Autodesk Fusion 360 part; units mm, degrees
(part 8 of 9)
equation "d522 = abs(( 0 ) * ( ( ( -1 ) * jointNodeQ * sqrt(2) - bodyWidth / 2 * cos(225 deg) + ( ( 1 ) * nodeHalfWidth ) * sin(225 deg) ) + ( 0.666666666666667 ) * ( ( -1 ) * endNodeX - ( ( -1 ) * jointNodeQ * sqrt(2) - bodyWidth / 2 * cos(225 deg) + ( ( 1 ) * nodeHalfWidth ) * sin(225 deg) ) ) ) + ( -1 ) * ( ( 1 ) * nodeHalfWidth ))"
equation "d523 = abs(( 1 ) * ( ( ( -1 ) * jointNodeQ * sqrt(2) - bodyWidth / 2 * cos(225 deg) + ( ( -1 ) * nodeHalfWidth ) * sin(225 deg) ) + ( 1 ) * ( ( -1 ) * endNodeX - ( ( -1 ) * jointNodeQ * sqrt(2) - bodyWidth / 2 * cos(225 deg) + ( ( -1 ) * nodeHalfWidth ) * sin(225 deg) ) ) ) + ( 0 ) * ( ( -1 ) * nodeHalfWidth ))"
equation "d524 = abs(( 0 ) * ( ( ( -1 ) * jointNodeQ * sqrt(2) - bodyWidth / 2 * cos(225 deg) + ( ( -1 ) * nodeHalfWidth ) * sin(225 deg) ) + ( 1 ) * ( ( -1 ) * endNodeX - ( ( -1 ) * jointNodeQ * sqrt(2) - bodyWidth / 2 * cos(225 deg) + ( ( -1 ) * nodeHalfWidth ) * sin(225 deg) ) ) ) + ( -1 ) * ( ( -1 ) * nodeHalfWidth ))"
equation "d525 = memberWidth / 2"
equation "d526 = -( wall + 0.2 mm )"
equation "d528 = abs(( 1 ) * ( ( ( -1 ) * jointNodeQ * sqrt(2) - bodyWidth / 2 * cos(225 deg) + ( ( 1 ) * nodeHalfWidth ) * sin(225 deg) ) + ( 0.666666666666667 ) * ( ( -1 ) * endNodeX - ( ( -1 ) * jointNodeQ * sqrt(2) - bodyWidth / 2 * cos(225 deg) + ( ( 1 ) * nodeHalfWidth ) * sin(225 deg) ) ) ) + ( 0 ) * ( ( 1 ) * nodeHalfWidth ))"
equation "d529 = abs(( 0 ) * ( ( ( -1 ) * jointNodeQ * sqrt(2) - bodyWidth / 2 * cos(225 deg) + ( ( 1 ) * nodeHalfWidth ) * sin(225 deg) ) + ( 0.666666666666667 ) * ( ( -1 ) * endNodeX - ( ( -1 ) * jointNodeQ * sqrt(2) - bodyWidth / 2 * cos(225 deg) + ( ( 1 ) * nodeHalfWidth ) * sin(225 deg) ) ) ) + ( -1 ) * ( ( 1 ) * nodeHalfWidth ))"
equation "d530 = abs(( 1 ) * ( ( ( -1 ) * jointNodeQ * sqrt(2) - bodyWidth / 2 * cos(225 deg) + ( ( -1 ) * nodeHalfWidth ) * sin(225 deg) ) + ( 1 ) * ( ( -1 ) * endNodeX - ( ( -1 ) * jointNodeQ * sqrt(2) - bodyWidth / 2 * cos(225 deg) + ( ( -1 ) * nodeHalfWidth ) * sin(225 deg) ) ) ) + ( 0 ) * ( ( -1 ) * nodeHalfWidth ))"
equation "d531 = abs(( 0 ) * ( ( ( -1 ) * jointNodeQ * sqrt(2) - bodyWidth / 2 * cos(225 deg) + ( ( -1 ) * nodeHalfWidth ) * sin(225 deg) ) + ( 1 ) * ( ( -1 ) * endNodeX - ( ( -1 ) * jointNodeQ * sqrt(2) - bodyWidth / 2 * cos(225 deg) + ( ( -1 ) * nodeHalfWidth ) * sin(225 deg) ) ) ) + ( -1 ) * ( ( -1 ) * nodeHalfWidth ))"
equation "d532 = abs(( 1 ) * ( ( ( -1 ) * jointNodeQ * sqrt(2) - bodyWidth / 2 * cos(225 deg) + ( ( 1 ) * nodeHalfWidth ) * sin(225 deg) ) + ( 1 ) * ( ( -1 ) * endNodeX - ( ( -1 ) * jointNodeQ * sqrt(2) - bodyWidth / 2 * cos(225 deg) + ( ( 1 ) * nodeHalfWidth ) * sin(225 deg) ) ) ) + ( 0 ) * ( ( 1 ) * nodeHalfWidth ))"
equation "d533 = abs(( 0 ) * ( ( ( -1 ) * jointNodeQ * sqrt(2) - bodyWidth / 2 * cos(225 deg) + ( ( 1 ) * nodeHalfWidth ) * sin(225 deg) ) + ( 1 ) * ( ( -1 ) * endNodeX - ( ( -1 ) * jointNodeQ * sqrt(2) - bodyWidth / 2 * cos(225 deg) + ( ( 1 ) * nodeHalfWidth ) * sin(225 deg) ) ) ) + ( -1 ) * ( ( 1 ) * nodeHalfWidth ))"
equation "d534 = -memberWidth / 2"
equation "d535 = -( wall + 0.2 mm )"
equation "d538 = apertureRadius"
equation "d541 = bodyWidth / 2"
equation "d543 = abs(( -1 ) * ( ( ( -1 ) * jointNodeQ * sqrt(2) - bodyWidth / 2 * cos(270 deg) + ( ( -1 ) * nodeHalfWidth ) * sin(270 deg) ) + ( 0 ) * ( ( -1 ) * endNodeX - ( ( -1 ) * jointNodeQ * sqrt(2) - bodyWidth / 2 * cos(270 deg) + ( ( -1 ) * nodeHalfWidth ) * sin(270 deg) ) ) ) + ( 0 ) * ( ( -1 ) * nodeHalfWidth ))"
equation "d544 = abs(( 0 ) * ( ( ( -1 ) * jointNodeQ * sqrt(2) - bodyWidth / 2 * cos(270 deg) + ( ( -1 ) * nodeHalfWidth ) * sin(270 deg) ) + ( 0 ) * ( ( -1 ) * endNodeX - ( ( -1 ) * jointNodeQ * sqrt(2) - bodyWidth / 2 * cos(270 deg) + ( ( -1 ) * nodeHalfWidth ) * sin(270 deg) ) ) ) + ( 1 ) * ( ( -1 ) * nodeHalfWidth ))"
equation "d545 = abs(( -1 ) * ( ( ( -1 ) * jointNodeQ * sqrt(2) - bodyWidth / 2 * cos(270 deg) + ( ( 1 ) * nodeHalfWidth ) * sin(270 deg) ) + ( 0 ) * ( ( -1 ) * endNodeX - ( ( -1 ) * jointNodeQ * sqrt(2) - bodyWidth / 2 * cos(270 deg) + ( ( 1 ) * nodeHalfWidth ) * sin(270 deg) ) ) ) + ( 0 ) * ( ( 1 ) * nodeHalfWidth ))"
equation "d546 = abs(( 0 ) * ( ( ( -1 ) * jointNodeQ * sqrt(2) - bodyWidth / 2 * cos(270 deg) + ( ( 1 ) * nodeHalfWidth ) * sin(270 deg) ) + ( 0 ) * ( ( -1 ) * endNodeX - ( ( -1 ) * jointNodeQ * sqrt(2) - bodyWidth / 2 * cos(270 deg) + ( ( 1 ) * nodeHalfWidth ) * sin(270 deg) ) ) ) + ( 1 ) * ( ( 1 ) * nodeHalfWidth ))"
equation "d547 = abs(( -1 ) * ( ( ( -1 ) * jointNodeQ * sqrt(2) - bodyWidth / 2 * cos(270 deg) + ( ( -1 ) * nodeHalfWidth ) * sin(270 deg) ) + ( 0.5 ) * ( ( -1 ) * endNodeX - ( ( -1 ) * jointNodeQ * sqrt(2) - bodyWidth / 2 * cos(270 deg) + ( ( -1 ) * nodeHalfWidth ) * sin(270 deg) ) ) ) + ( 0 ) * ( ( -1 ) * nodeHalfWidth ))"
equation "d548 = abs(( 0 ) * ( ( ( -1 ) * jointNodeQ * sqrt(2) - bodyWidth / 2 * cos(270 deg) + ( ( -1 ) * nodeHalfWidth ) * sin(270 deg) ) + ( 0.5 ) * ( ( -1 ) * endNodeX - ( ( -1 ) * jointNodeQ * sqrt(2) - bodyWidth / 2 * cos(270 deg) + ( ( -1 ) * nodeHalfWidth ) * sin(270 deg) ) ) ) + ( 1 ) * ( ( -1 ) * nodeHalfWidth ))"
equation "d549 = memberWidth / 2"
equation "d550 = -( wall + 0.2 mm )"
equation "d552 = abs(( -1 ) * ( ( ( -1 ) * jointNodeQ * sqrt(2) - bodyWidth / 2 * cos(270 deg) + ( ( 1 ) * nodeHalfWidth ) * sin(270 deg) ) + ( 0 ) * ( ( -1 ) * endNodeX - ( ( -1 ) * jointNodeQ * sqrt(2) - bodyWidth / 2 * cos(270 deg) + ( ( 1 ) * nodeHalfWidth ) * sin(270 deg) ) ) ) + ( 0 ) * ( ( 1 ) * nodeHalfWidth ))"
equation "d553 = abs(( 0 ) * ( ( ( -1 ) * jointNodeQ * sqrt(2) - bodyWidth / 2 * cos(270 deg) + ( ( 1 ) * nodeHalfWidth ) * sin(270 deg) ) + ( 0 ) * ( ( -1 ) * endNodeX - ( ( -1 ) * jointNodeQ * sqrt(2) - bodyWidth / 2 * cos(270 deg) + ( ( 1 ) * nodeHalfWidth ) * sin(270 deg) ) ) ) + ( 1 ) * ( ( 1 ) * nodeHalfWidth ))"
equation "d554 = abs(( -1 ) * ( ( ( -1 ) * jointNodeQ * sqrt(2) - bodyWidth / 2 * cos(270 deg) + ( ( -1 ) * nodeHalfWidth ) * sin(270 deg) ) + ( 0.5 ) * ( ( -1 ) * endNodeX - ( ( -1 ) * jointNodeQ * sqrt(2) - bodyWidth / 2 * cos(270 deg) + ( ( -1 ) * nodeHalfWidth ) * sin(270 deg) ) ) ) + ( 0 ) * ( ( -1 ) * nodeHalfWidth ))"
equation "d555 = abs(( 0 ) * ( ( ( -1 ) * jointNodeQ * sqrt(2) - bodyWidth / 2 * cos(270 deg) + ( ( -1 ) * nodeHalfWidth ) * sin(270 deg) ) + ( 0.5 ) * ( ( -1 ) * endNodeX - ( ( -1 ) * jointNodeQ * sqrt(2) - bodyWidth / 2 * cos(270 deg) + ( ( -1 ) * nodeHalfWidth ) * sin(270 deg) ) ) ) + ( 1 ) * ( ( -1 ) * nodeHalfWidth ))"
equation "d556 = abs(( -1 ) * ( ( ( -1 ) * jointNodeQ * sqrt(2) - bodyWidth / 2 * cos(270 deg) + ( ( 1 ) * nodeHalfWidth ) * sin(270 deg) ) + ( 1 ) * ( ( -1 ) * endNodeX - ( ( -1 ) * jointNodeQ * sqrt(2) - bodyWidth / 2 * cos(270 deg) + ( ( 1 ) * nodeHalfWidth ) * sin(270 deg) ) ) ) + ( 0 ) * ( ( 1 ) * nodeHalfWidth ))"
equation "d557 = abs(( 0 ) * ( ( ( -1 ) * jointNodeQ * sqrt(2) - bodyWidth / 2 * cos(270 deg) + ( ( 1 ) * nodeHalfWidth ) * sin(270 deg) ) + ( 1 ) * ( ( -1 ) * endNodeX - ( ( -1 ) * jointNodeQ * sqrt(2) - bodyWidth / 2 * cos(270 deg) + ( ( 1 ) * nodeHalfWidth ) * sin(270 deg) ) ) ) + ( 1 ) * ( ( 1 ) * nodeHalfWidth ))"
equation "d558 = -memberWidth / 2"
equation "d559 = -( wall + 0.2 mm )"
equation "d561 = abs(( -1 ) * ( ( ( -1 ) * jointNodeQ * sqrt(2) - bodyWidth / 2 * cos(270 deg) + ( ( -1 ) * nodeHalfWidth ) * sin(270 deg) ) + ( 0.5 ) * ( ( -1 ) * endNodeX - ( ( -1 ) * jointNodeQ * sqrt(2) - bodyWidth / 2 * cos(270 deg) + ( ( -1 ) * nodeHalfWidth ) * sin(270 deg) ) ) ) + ( 0 ) * ( ( -1 ) * nodeHalfWidth ))"
equation "d562 = abs(( 0 ) * ( ( ( -1 ) * jointNodeQ * sqrt(2) - bodyWidth / 2 * cos(270 deg) + ( ( -1 ) * nodeHalfWidth ) * sin(270 deg) ) + ( 0.5 ) * ( ( -1 ) * endNodeX - ( ( -1 ) * jointNodeQ * sqrt(2) - bodyWidth / 2 * cos(270 deg) + ( ( -1 ) * nodeHalfWidth ) * sin(270 deg) ) ) ) + ( 1 ) * ( ( -1 ) * nodeHalfWidth ))"
equation "d563 = abs(( -1 ) * ( ( ( -1 ) * jointNodeQ * sqrt(2) - bodyWidth / 2 * cos(270 deg) + ( ( 1 ) * nodeHalfWidth ) * sin(270 deg) ) + ( 1 ) * ( ( -1 ) * endNodeX - ( ( -1 ) * jointNodeQ * sqrt(2) - bodyWidth / 2 * cos(270 deg) + ( ( 1 ) * nodeHalfWidth ) * sin(270 deg) ) ) ) + ( 0 ) * ( ( 1 ) * nodeHalfWidth ))"
equation "d564 = abs(( 0 ) * ( ( ( -1 ) * jointNodeQ * sqrt(2) - bodyWidth / 2 * cos(270 deg) + ( ( 1 ) * nodeHalfWidth ) * sin(270 deg) ) + ( 1 ) * ( ( -1 ) * endNodeX - ( ( -1 ) * jointNodeQ * sqrt(2) - bodyWidth / 2 * cos(270 deg) + ( ( 1 ) * nodeHalfWidth ) * sin(270 deg) ) ) ) + ( 1 ) * ( ( 1 ) * nodeHalfWidth ))"
equation "d565 = abs(( -1 ) * ( ( ( -1 ) * jointNodeQ * sqrt(2) - bodyWidth / 2 * cos(270 deg) + ( ( -1 ) * nodeHalfWidth ) * sin(270 deg) ) + ( 1 ) * ( ( -1 ) * endNodeX - ( ( -1 ) * jointNodeQ * sqrt(2) - bodyWidth / 2 * cos(270 deg) + ( ( -1 ) * nodeHalfWidth ) * sin(270 deg) ) ) ) + ( 0 ) * ( ( -1 ) * nodeHalfWidth ))"
equation "d566 = abs(( 0 ) * ( ( ( -1 ) * jointNodeQ * sqrt(2) - bodyWidth / 2 * cos(270 deg) + ( ( -1 ) * nodeHalfWidth ) * sin(270 deg) ) + ( 1 ) * ( ( -1 ) * endNodeX - ( ( -1 ) * jointNodeQ * sqrt(2) - bodyWidth / 2 * cos(270 deg) + ( ( -1 ) * nodeHalfWidth ) * sin(270 deg) ) ) ) + ( 1 ) * ( ( -1 ) * nodeHalfWidth ))"
equation "d567 = memberWidth / 2"
equation "d568 = -( wall + 0.2 mm )"
equation "d571 = apertureRadius"
equation "d574 = bodyWidth / 2"
equation "d576 = abs(( 1 ) * ( ( ( -1 ) * jointNodeQ * sqrt(2) - bodyWidth / 2 * cos(315 deg) + ( ( -1 ) * nodeHalfWidth ) * sin(315 deg) ) + ( 0 ) * ( ( -1 ) * endNodeX - ( ( -1 ) * jointNodeQ * sqrt(2) - bodyWidth / 2 * cos(315 deg) + ( ( -1 ) * nodeHalfWidth ) * sin(315 deg) ) ) ) + ( 0 ) * ( ( -1 ) * nodeHalfWidth ))"
equation "d577 = abs(( 0 ) * ( ( ( -1 ) * jointNodeQ * sqrt(2) - bodyWidth / 2 * cos(315 deg) + ( ( -1 ) * nodeHalfWidth ) * sin(315 deg) ) + ( 0 ) * ( ( -1 ) * endNodeX - ( ( -1 ) * jointNodeQ * sqrt(2) - bodyWidth / 2 * cos(315 deg) + ( ( -1 ) * nodeHalfWidth ) * sin(315 deg) ) ) ) + ( -1 ) * ( ( -1 ) * nodeHalfWidth ))"
equation "d578 = abs(( 1 ) * ( ( ( -1 ) * jointNodeQ * sqrt(2) - bodyWidth / 2 * cos(315 deg) + ( ( 1 ) * nodeHalfWidth ) * sin(315 deg) ) + ( 0 ) * ( ( -1 ) * endNodeX - ( ( -1 ) * jointNodeQ * sqrt(2) - bodyWidth / 2 * cos(315 deg) + ( ( 1 ) * nodeHalfWidth ) * sin(315 deg) ) ) ) + ( 0 ) * ( ( 1 ) * nodeHalfWidth ))"
equation "d579 = abs(( 0 ) * ( ( ( -1 ) * jointNodeQ * sqrt(2) - bodyWidth / 2 * cos(315 deg) + ( ( 1 ) * nodeHalfWidth ) * sin(315 deg) ) + ( 0 ) * ( ( -1 ) * endNodeX - ( ( -1 ) * jointNodeQ * sqrt(2) - bodyWidth / 2 * cos(315 deg) + ( ( 1 ) * nodeHalfWidth ) * sin(315 deg) ) ) ) + ( -1 ) * ( ( 1 ) * nodeHalfWidth ))"
equation "d580 = abs(( 1 ) * ( ( ( -1 ) * jointNodeQ * sqrt(2) - bodyWidth / 2 * cos(315 deg) + ( ( -1 ) * nodeHalfWidth ) * sin(315 deg) ) + ( 1 ) * ( ( -1 ) * endNodeX - ( ( -1 ) * jointNodeQ * sqrt(2) - bodyWidth / 2 * cos(315 deg) + ( ( -1 ) * nodeHalfWidth ) * sin(315 deg) ) ) ) + ( 0 ) * ( ( -1 ) * nodeHalfWidth ))"
equation "d581 = abs(( 0 ) * ( ( ( -1 ) * jointNodeQ * sqrt(2) - bodyWidth / 2 * cos(315 deg) + ( ( -1 ) * nodeHalfWidth ) * sin(315 deg) ) + ( 1 ) * ( ( -1 ) * endNodeX - ( ( -1 ) * jointNodeQ * sqrt(2) - bodyWidth / 2 * cos(315 deg) + ( ( -1 ) * nodeHalfWidth ) * sin(315 deg) ) ) ) + ( -1 ) * ( ( -1 ) * nodeHalfWidth ))"
equation "d582 = memberWidth / 2"
equation "d583 = -( wall + 0.2 mm )"
equation "d585 = abs(( 1 ) * ( ( ( -1 ) * jointNodeQ * sqrt(2) - bodyWidth / 2 * cos(315 deg) + ( ( 1 ) * nodeHalfWidth ) * sin(315 deg) ) + ( 0 ) * ( ( -1 ) * endNodeX - ( ( -1 ) * jointNodeQ * sqrt(2) - bodyWidth / 2 * cos(315 deg) + ( ( 1 ) * nodeHalfWidth ) * sin(315 deg) ) ) ) + ( 0 ) * ( ( 1 ) * nodeHalfWidth ))"
equation "d586 = abs(( 0 ) * ( ( ( -1 ) * jointNodeQ * sqrt(2) - bodyWidth / 2 * cos(315 deg) + ( ( 1 ) * nodeHalfWidth ) * sin(315 deg) ) + ( 0 ) * ( ( -1 ) * endNodeX - ( ( -1 ) * jointNodeQ * sqrt(2) - bodyWidth / 2 * cos(315 deg) + ( ( 1 ) * nodeHalfWidth ) * sin(315 deg) ) ) ) + ( -1 ) * ( ( 1 ) * nodeHalfWidth ))"
equation "d587 = abs(( 1 ) * ( ( ( -1 ) * jointNodeQ * sqrt(2) - bodyWidth / 2 * cos(315 deg) + ( ( -1 ) * nodeHalfWidth ) * sin(315 deg) ) + ( 1 ) * ( ( -1 ) * endNodeX - ( ( -1 ) * jointNodeQ * sqrt(2) - bodyWidth / 2 * cos(315 deg) + ( ( -1 ) * nodeHalfWidth ) * sin(315 deg) ) ) ) + ( 0 ) * ( ( -1 ) * nodeHalfWidth ))"
equation "d588 = abs(( 0 ) * ( ( ( -1 ) * jointNodeQ * sqrt(2) - bodyWidth / 2 * cos(315 deg) + ( ( -1 ) * nodeHalfWidth ) * sin(315 deg) ) + ( 1 ) * ( ( -1 ) * endNodeX - ( ( -1 ) * jointNodeQ * sqrt(2) - bodyWidth / 2 * cos(315 deg) + ( ( -1 ) * nodeHalfWidth ) * sin(315 deg) ) ) ) + ( -1 ) * ( ( -1 ) * nodeHalfWidth ))"
equation "d589 = abs(( 1 ) * ( ( ( -1 ) * jointNodeQ * sqrt(2) - bodyWidth / 2 * cos(315 deg) + ( ( 1 ) * nodeHalfWidth ) * sin(315 deg) ) + ( 1 ) * ( ( -1 ) * endNodeX - ( ( -1 ) * jointNodeQ * sqrt(2) - bodyWidth / 2 * cos(315 deg) + ( ( 1 ) * nodeHalfWidth ) * sin(315 deg) ) ) ) + ( 0 ) * ( ( 1 ) * nodeHalfWidth ))"
equation "d590 = abs(( 0 ) * ( ( ( -1 ) * jointNodeQ * sqrt(2) - bodyWidth / 2 * cos(315 deg) + ( ( 1 ) * nodeHalfWidth ) * sin(315 deg) ) + ( 1 ) * ( ( -1 ) * endNodeX - ( ( -1 ) * jointNodeQ * sqrt(2) - bodyWidth / 2 * cos(315 deg) + ( ( 1 ) * nodeHalfWidth ) * sin(315 deg) ) ) ) + ( -1 ) * ( ( 1 ) * nodeHalfWidth ))"
equation "d591 = -memberWidth / 2"
equation "d592 = -( wall + 0.2 mm )"
equation "d595 = apertureRadius"
equation "d596 = qFront"
equation "d598 = carrierOD"
equation "d599 = spokeDepth"
equation "d601 = qFront"
equation "d603 = abs(( 0 mm ) * ( cos(-73.6750500631048 deg) ) - ( -1 ) * spokeWidth / 2 * ( sin(-73.6750500631048 deg) ))"
equation "d604 = abs(( 0 mm ) * ( sin(-73.6750500631048 deg) ) + ( -1 ) * spokeWidth / 2 * ( cos(-73.6750500631048 deg) ))"
equation "d605 = abs(( bodyWidth ) * ( cos(-73.6750500631048 deg) ) - ( -1 ) * spokeWidth / 2 * ( sin(-73.6750500631048 deg) ))"
equation "d606 = abs(( bodyWidth ) * ( sin(-73.6750500631048 deg) ) + ( -1 ) * spokeWidth / 2 * ( cos(-73.6750500631048 deg) ))"
equation "d607 = abs(( bodyWidth ) * ( cos(-73.6750500631048 deg) ) - ( 1 ) * spokeWidth / 2 * ( sin(-73.6750500631048 deg) ))"
equation "d608 = abs(( bodyWidth ) * ( sin(-73.6750500631048 deg) ) + ( 1 ) * spokeWidth / 2 * ( cos(-73.6750500631048 deg) ))"
equation "d609 = abs(( 0 mm ) * ( cos(-73.6750500631048 deg) ) - ( 1 ) * spokeWidth / 2 * ( sin(-73.6750500631048 deg) ))"
equation "d610 = abs(( 0 mm ) * ( sin(-73.6750500631048 deg) ) + ( 1 ) * spokeWidth / 2 * ( cos(-73.6750500631048 deg) ))"
equation "d611 = spokeDepth"
equation "d613 = abs(( 0 mm ) * ( cos(-30.3611934048217 deg) ) - ( -1 ) * spokeWidth / 2 * ( sin(-30.3611934048217 deg) ))"
equation "d614 = abs(( 0 mm ) * ( sin(-30.3611934048217 deg) ) + ( -1 ) * spokeWidth / 2 * ( cos(-30.3611934048217 deg) ))"
equation "d615 = abs(( bodyWidth ) * ( cos(-30.3611934048217 deg) ) - ( -1 ) * spokeWidth / 2 * ( sin(-30.3611934048217 deg) ))"
equation "d616 = abs(( bodyWidth ) * ( sin(-30.3611934048217 deg) ) + ( -1 ) * spokeWidth / 2 * ( cos(-30.3611934048217 deg) ))"
equation "d617 = abs(( bodyWidth ) * ( cos(-30.3611934048217 deg) ) - ( 1 ) * spokeWidth / 2 * ( sin(-30.3611934048217 deg) ))"
equation "d618 = abs(( bodyWidth ) * ( sin(-30.3611934048217 deg) ) + ( 1 ) * spokeWidth / 2 * ( cos(-30.3611934048217 deg) ))"
equation "d619 = abs(( 0 mm ) * ( cos(-30.3611934048217 deg) ) - ( 1 ) * spokeWidth / 2 * ( sin(-30.3611934048217 deg) ))"
equation "d620 = abs(( 0 mm ) * ( sin(-30.3611934048217 deg) ) + ( 1 ) * spokeWidth / 2 * ( cos(-30.3611934048217 deg) ))"
equation "d621 = spokeDepth"
equation "d623 = abs(( 0 mm ) * ( cos(30.3611934048217 deg) ) - ( -1 ) * spokeWidth / 2 * ( sin(30.3611934048217 deg) ))"
equation "d624 = abs(( 0 mm ) * ( sin(30.3611934048217 deg) ) + ( -1 ) * spokeWidth / 2 * ( cos(30.3611934048217 deg) ))"
equation "d625 = abs(( bodyWidth ) * ( cos(30.3611934048217 deg) ) - ( -1 ) * spokeWidth / 2 * ( sin(30.3611934048217 deg) ))"
equation "d626 = abs(( bodyWidth ) * ( sin(30.3611934048217 deg) ) + ( -1 ) * spokeWidth / 2 * ( cos(30.3611934048217 deg) ))"
equation "d627 = abs(( bodyWidth ) * ( cos(30.3611934048217 deg) ) - ( 1 ) * spokeWidth / 2 * ( sin(30.3611934048217 deg) ))"
equation "d628 = abs(( bodyWidth ) * ( sin(30.3611934048217 deg) ) + ( 1 ) * spokeWidth / 2 * ( cos(30.3611934048217 deg) ))"
equation "d629 = abs(( 0 mm ) * ( cos(30.3611934048217 deg) ) - ( 1 ) * spokeWidth / 2 * ( sin(30.3611934048217 deg) ))"
equation "d630 = abs(( 0 mm ) * ( sin(30.3611934048217 deg) ) + ( 1 ) * spokeWidth / 2 * ( cos(30.3611934048217 deg) ))"
equation "d631 = spokeDepth"
equation "d633 = abs(( 0 mm ) * ( cos(73.6750500631048 deg) ) - ( -1 ) * spokeWidth / 2 * ( sin(73.6750500631048 deg) ))"
equation "d634 = abs(( 0 mm ) * ( sin(73.6750500631048 deg) ) + ( -1 ) * spokeWidth / 2 * ( cos(73.6750500631048 deg) ))"
equation "d635 = abs(( bodyWidth ) * ( cos(73.6750500631048 deg) ) - ( -1 ) * spokeWidth / 2 * ( sin(73.6750500631048 deg) ))"
equation "d636 = abs(( bodyWidth ) * ( sin(73.6750500631048 deg) ) + ( -1 ) * spokeWidth / 2 * ( cos(73.6750500631048 deg) ))"
equation "d637 = abs(( bodyWidth ) * ( cos(73.6750500631048 deg) ) - ( 1 ) * spokeWidth / 2 * ( sin(73.6750500631048 deg) ))"
equation "d638 = abs(( bodyWidth ) * ( sin(73.6750500631048 deg) ) + ( 1 ) * spokeWidth / 2 * ( cos(73.6750500631048 deg) ))"
equation "d639 = abs(( 0 mm ) * ( cos(73.6750500631048 deg) ) - ( 1 ) * spokeWidth / 2 * ( sin(73.6750500631048 deg) ))"
equation "d640 = abs(( 0 mm ) * ( sin(73.6750500631048 deg) ) + ( 1 ) * spokeWidth / 2 * ( cos(73.6750500631048 deg) ))"
equation "d641 = spokeDepth"
equation "d643 = abs(( 0 mm ) * ( cos(106.324949936895 deg) ) - ( -1 ) * spokeWidth / 2 * ( sin(106.324949936895 deg) ))"
equation "d644 = abs(( 0 mm ) * ( sin(106.324949936895 deg) ) + ( -1 ) * spokeWidth / 2 * ( cos(106.324949936895 deg) ))"
equation "d645 = abs(( bodyWidth ) * ( cos(106.324949936895 deg) ) - ( -1 ) * spokeWidth / 2 * ( sin(106.324949936895 deg) ))"
equation "d646 = abs(( bodyWidth ) * ( sin(106.324949936895 deg) ) + ( -1 ) * spokeWidth / 2 * ( cos(106.324949936895 deg) ))"
equation "d647 = abs(( bodyWidth ) * ( cos(106.324949936895 deg) ) - ( 1 ) * spokeWidth / 2 * ( sin(106.324949936895 deg) ))"
equation "d648 = abs(( bodyWidth ) * ( sin(106.324949936895 deg) ) + ( 1 ) * spokeWidth / 2 * ( cos(106.324949936895 deg) ))"
equation "d649 = abs(( 0 mm ) * ( cos(106.324949936895 deg) ) - ( 1 ) * spokeWidth / 2 * ( sin(106.324949936895 deg) ))"
equation "d650 = abs(( 0 mm ) * ( sin(106.324949936895 deg) ) + ( 1 ) * spokeWidth / 2 * ( cos(106.324949936895 deg) ))"
equation "d651 = spokeDepth"
equation "d653 = abs(( 0 mm ) * ( cos(149.638806595178 deg) ) - ( -1 ) * spokeWidth / 2 * ( sin(149.638806595178 deg) ))"
equation "d654 = abs(( 0 mm ) * ( sin(149.638806595178 deg) ) + ( -1 ) * spokeWidth / 2 * ( cos(149.638806595178 deg) ))"
equation "d655 = abs(( bodyWidth ) * ( cos(149.638806595178 deg) ) - ( -1 ) * spokeWidth / 2 * ( sin(149.638806595178 deg) ))"
equation "d656 = abs(( bodyWidth ) * ( sin(149.638806595178 deg) ) + ( -1 ) * spokeWidth / 2 * ( cos(149.638806595178 deg) ))"
equation "d657 = abs(( bodyWidth ) * ( cos(149.638806595178 deg) ) - ( 1 ) * spokeWidth / 2 * ( sin(149.638806595178 deg) ))"
equation "d658 = abs(( bodyWidth ) * ( sin(149.638806595178 deg) ) + ( 1 ) * spokeWidth / 2 * ( cos(149.638806595178 deg) ))"
equation "d659 = abs(( 0 mm ) * ( cos(149.638806595178 deg) ) - ( 1 ) * spokeWidth / 2 * ( sin(149.638806595178 deg) ))"
equation "d660 = abs(( 0 mm ) * ( sin(149.638806595178 deg) ) + ( 1 ) * spokeWidth / 2 * ( cos(149.638806595178 deg) ))"
equation "d661 = spokeDepth"
equation "d663 = abs(( 0 mm ) * ( cos(-149.638806595178 deg) ) - ( -1 ) * spokeWidth / 2 * ( sin(-149.638806595178 deg) ))"
equation "d664 = abs(( 0 mm ) * ( sin(-149.638806595178 deg) ) + ( -1 ) * spokeWidth / 2 * ( cos(-149.638806595178 deg) ))"
equation "d665 = abs(( bodyWidth ) * ( cos(-149.638806595178 deg) ) - ( -1 ) * spokeWidth / 2 * ( sin(-149.638806595178 deg) ))"
equation "d666 = abs(( bodyWidth ) * ( sin(-149.638806595178 deg) ) + ( -1 ) * spokeWidth / 2 * ( cos(-149.638806595178 deg) ))"
equation "d667 = abs(( bodyWidth ) * ( cos(-149.638806595178 deg) ) - ( 1 ) * spokeWidth / 2 * ( sin(-149.638806595178 deg) ))"
equation "d668 = abs(( bodyWidth ) * ( sin(-149.638806595178 deg) ) + ( 1 ) * spokeWidth / 2 * ( cos(-149.638806595178 deg) ))"
equation "d669 = abs(( 0 mm ) * ( cos(-149.638806595178 deg) ) - ( 1 ) * spokeWidth / 2 * ( sin(-149.638806595178 deg) ))"
equation "d670 = abs(( 0 mm ) * ( sin(-149.638806595178 deg) ) + ( 1 ) * spokeWidth / 2 * ( cos(-149.638806595178 deg) ))"
equation "d671 = spokeDepth"
equation "d673 = abs(( 0 mm ) * ( cos(-106.324949936895 deg) ) - ( -1 ) * spokeWidth / 2 * ( sin(-106.324949936895 deg) ))"
equation "d674 = abs(( 0 mm ) * ( sin(-106.324949936895 deg) ) + ( -1 ) * spokeWidth / 2 * ( cos(-106.324949936895 deg) ))"
equation "d675 = abs(( bodyWidth ) * ( cos(-106.324949936895 deg) ) - ( -1 ) * spokeWidth / 2 * ( sin(-106.324949936895 deg) ))"
equation "d676 = abs(( bodyWidth ) * ( sin(-106.324949936895 deg) ) + ( -1 ) * spokeWidth / 2 * ( cos(-106.324949936895 deg) ))"
equation "d677 = abs(( bodyWidth ) * ( cos(-106.324949936895 deg) ) - ( 1 ) * spokeWidth / 2 * ( sin(-106.324949936895 deg) ))"
equation "d678 = abs(( bodyWidth ) * ( sin(-106.324949936895 deg) ) + ( 1 ) * spokeWidth / 2 * ( cos(-106.324949936895 deg) ))"
equation "d679 = abs(( 0 mm ) * ( cos(-106.324949936895 deg) ) - ( 1 ) * spokeWidth / 2 * ( sin(-106.324949936895 deg) ))"
equation "d680 = abs(( 0 mm ) * ( sin(-106.324949936895 deg) ) + ( 1 ) * spokeWidth / 2 * ( cos(-106.324949936895 deg) ))"
equation "d681 = spokeDepth"
equation "d683 = bodyWidth"
equation "d684 = bodyLength"
equation "d687 = rootRadius"
equation "d688 = qFrontBack"
equation "d690 = rearCarrierClearance"
equation "d691 = spokeDepth"
equation "d693 = qFront"
equation "d695 = raceRelief"
equation "d696 = frontSeatDepth + shoulder"
equation "d698 = qFront"
equation "d700 = seatDiameter"
equation "d701 = frontSeatDepth"
equation "d703 = qFront"
equation "d705 = supportCircle / 2"
equation "d706 = m3Clearance"
equation "d707 = frontSeatDepth + shoulder"
equation "d711 = qFront"
equation "d713 = coreOD"
equation "d714 = entryChamfer"
equation "d715 = bodyWidth / 2"
equation "d717 = abs(( 16 mm + ( -6.5 mm ) ) / sqrt(2))"
equation "d718 = abs(( 16 mm - ( -6.5 mm ) ) / sqrt(2))"
equation "d720 = abs(( 16 mm + ( 6.5 mm ) ) / sqrt(2))"
equation "d721 = abs(( 16 mm - ( 6.5 mm ) ) / sqrt(2))"
equation "d723 = -( bodyWidth / 2 )"
equation "d725 = -qFront"
equation "d727 = mountOD"
equation "d728 = -( -qFront - hubFace )"
equation "d730 = -qFront"
equation "d732 = abs(( 0 mm ) * ( cos(-73.6750500631048 deg) ) - ( -1 ) * spokeWidth / 2 * ( sin(-73.6750500631048 deg) ))"
equation "d733 = abs(( 0 mm ) * ( sin(-73.6750500631048 deg) ) + ( -1 ) * spokeWidth / 2 * ( cos(-73.6750500631048 deg) ))"
equation "d734 = abs(( bodyWidth ) * ( cos(-73.6750500631048 deg) ) - ( -1 ) * spokeWidth / 2 * ( sin(-73.6750500631048 deg) ))"
equation "d735 = abs(( bodyWidth ) * ( sin(-73.6750500631048 deg) ) + ( -1 ) * spokeWidth / 2 * ( cos(-73.6750500631048 deg) ))"
equation "d736 = abs(( bodyWidth ) * ( cos(-73.6750500631048 deg) ) - ( 1 ) * spokeWidth / 2 * ( sin(-73.6750500631048 deg) ))"
equation "d737 = abs(( bodyWidth ) * ( sin(-73.6750500631048 deg) ) + ( 1 ) * spokeWidth / 2 * ( cos(-73.6750500631048 deg) ))"
equation "d738 = abs(( 0 mm ) * ( cos(-73.6750500631048 deg) ) - ( 1 ) * spokeWidth / 2 * ( sin(-73.6750500631048 deg) ))"
equation "d739 = abs(( 0 mm ) * ( sin(-73.6750500631048 deg) ) + ( 1 ) * spokeWidth / 2 * ( cos(-73.6750500631048 deg) ))"
equation "d740 = -( spokeDepth )"
equation "d742 = abs(( 0 mm ) * ( cos(-30.3611934048217 deg) ) - ( -1 ) * spokeWidth / 2 * ( sin(-30.3611934048217 deg) ))"
equation "d743 = abs(( 0 mm ) * ( sin(-30.3611934048217 deg) ) + ( -1 ) * spokeWidth / 2 * ( cos(-30.3611934048217 deg) ))"
equation "d744 = abs(( bodyWidth ) * ( cos(-30.3611934048217 deg) ) - ( -1 ) * spokeWidth / 2 * ( sin(-30.3611934048217 deg) ))"
equation "d745 = abs(( bodyWidth ) * ( sin(-30.3611934048217 deg) ) + ( -1 ) * spokeWidth / 2 * ( cos(-30.3611934048217 deg) ))"
equation "d746 = abs(( bodyWidth ) * ( cos(-30.3611934048217 deg) ) - ( 1 ) * spokeWidth / 2 * ( sin(-30.3611934048217 deg) ))"
equation "d747 = abs(( bodyWidth ) * ( sin(-30.3611934048217 deg) ) + ( 1 ) * spokeWidth / 2 * ( cos(-30.3611934048217 deg) ))"
equation "d748 = abs(( 0 mm ) * ( cos(-30.3611934048217 deg) ) - ( 1 ) * spokeWidth / 2 * ( sin(-30.3611934048217 deg) ))"
equation "d749 = abs(( 0 mm ) * ( sin(-30.3611934048217 deg) ) + ( 1 ) * spokeWidth / 2 * ( cos(-30.3611934048217 deg) ))"
equation "d750 = -( spokeDepth )"
equation "d752 = abs(( 0 mm ) * ( cos(30.3611934048217 deg) ) - ( -1 ) * spokeWidth / 2 * ( sin(30.3611934048217 deg) ))"
equation "d753 = abs(( 0 mm ) * ( sin(30.3611934048217 deg) ) + ( -1 ) * spokeWidth / 2 * ( cos(30.3611934048217 deg) ))"
equation "d754 = abs(( bodyWidth ) * ( cos(30.3611934048217 deg) ) - ( -1 ) * spokeWidth / 2 * ( sin(30.3611934048217 deg) ))"
equation "d755 = abs(( bodyWidth ) * ( sin(30.3611934048217 deg) ) + ( -1 ) * spokeWidth / 2 * ( cos(30.3611934048217 deg) ))"
equation "d756 = abs(( bodyWidth ) * ( cos(30.3611934048217 deg) ) - ( 1 ) * spokeWidth / 2 * ( sin(30.3611934048217 deg) ))"
equation "d757 = abs(( bodyWidth ) * ( sin(30.3611934048217 deg) ) + ( 1 ) * spokeWidth / 2 * ( cos(30.3611934048217 deg) ))"
equation "d758 = abs(( 0 mm ) * ( cos(30.3611934048217 deg) ) - ( 1 ) * spokeWidth / 2 * ( sin(30.3611934048217 deg) ))"
equation "d759 = abs(( 0 mm ) * ( sin(30.3611934048217 deg) ) + ( 1 ) * spokeWidth / 2 * ( cos(30.3611934048217 deg) ))"
equation "d760 = -( spokeDepth )"
equation "d762 = abs(( 0 mm ) * ( cos(73.6750500631048 deg) ) - ( -1 ) * spokeWidth / 2 * ( sin(73.6750500631048 deg) ))"
equation "d763 = abs(( 0 mm ) * ( sin(73.6750500631048 deg) ) + ( -1 ) * spokeWidth / 2 * ( cos(73.6750500631048 deg) ))"
equation "d764 = abs(( bodyWidth ) * ( cos(73.6750500631048 deg) ) - ( -1 ) * spokeWidth / 2 * ( sin(73.6750500631048 deg) ))"
equation "d765 = abs(( bodyWidth ) * ( sin(73.6750500631048 deg) ) + ( -1 ) * spokeWidth / 2 * ( cos(73.6750500631048 deg) ))"
equation "d766 = abs(( bodyWidth ) * ( cos(73.6750500631048 deg) ) - ( 1 ) * spokeWidth / 2 * ( sin(73.6750500631048 deg) ))"
equation "d767 = abs(( bodyWidth ) * ( sin(73.6750500631048 deg) ) + ( 1 ) * spokeWidth / 2 * ( cos(73.6750500631048 deg) ))"
equation "d768 = abs(( 0 mm ) * ( cos(73.6750500631048 deg) ) - ( 1 ) * spokeWidth / 2 * ( sin(73.6750500631048 deg) ))"
equation "d769 = abs(( 0 mm ) * ( sin(73.6750500631048 deg) ) + ( 1 ) * spokeWidth / 2 * ( cos(73.6750500631048 deg) ))"
equation "d770 = -( spokeDepth )"
equation "d772 = abs(( 0 mm ) * ( cos(106.324949936895 deg) ) - ( -1 ) * spokeWidth / 2 * ( sin(106.324949936895 deg) ))"
equation "d773 = abs(( 0 mm ) * ( sin(106.324949936895 deg) ) + ( -1 ) * spokeWidth / 2 * ( cos(106.324949936895 deg) ))"
equation "d774 = abs(( bodyWidth ) * ( cos(106.324949936895 deg) ) - ( -1 ) * spokeWidth / 2 * ( sin(106.324949936895 deg) ))"
equation "d775 = abs(( bodyWidth ) * ( sin(106.324949936895 deg) ) + ( -1 ) * spokeWidth / 2 * ( cos(106.324949936895 deg) ))"
equation "d776 = abs(( bodyWidth ) * ( cos(106.324949936895 deg) ) - ( 1 ) * spokeWidth / 2 * ( sin(106.324949936895 deg) ))"
equation "d777 = abs(( bodyWidth ) * ( sin(106.324949936895 deg) ) + ( 1 ) * spokeWidth / 2 * ( cos(106.324949936895 deg) ))"
equation "d778 = abs(( 0 mm ) * ( cos(106.324949936895 deg) ) - ( 1 ) * spokeWidth / 2 * ( sin(106.324949936895 deg) ))"
equation "d779 = abs(( 0 mm ) * ( sin(106.324949936895 deg) ) + ( 1 ) * spokeWidth / 2 * ( cos(106.324949936895 deg) ))"
equation "d780 = -( spokeDepth )"
equation "d782 = abs(( 0 mm ) * ( cos(149.638806595178 deg) ) - ( -1 ) * spokeWidth / 2 * ( sin(149.638806595178 deg) ))"
equation "d783 = abs(( 0 mm ) * ( sin(149.638806595178 deg) ) + ( -1 ) * spokeWidth / 2 * ( cos(149.638806595178 deg) ))"
equation "d784 = abs(( bodyWidth ) * ( cos(149.638806595178 deg) ) - ( -1 ) * spokeWidth / 2 * ( sin(149.638806595178 deg) ))"
equation "d785 = abs(( bodyWidth ) * ( sin(149.638806595178 deg) ) + ( -1 ) * spokeWidth / 2 * ( cos(149.638806595178 deg) ))"
equation "d786 = abs(( bodyWidth ) * ( cos(149.638806595178 deg) ) - ( 1 ) * spokeWidth / 2 * ( sin(149.638806595178 deg) ))"
equation "d787 = abs(( bodyWidth ) * ( sin(149.638806595178 deg) ) + ( 1 ) * spokeWidth / 2 * ( cos(149.638806595178 deg) ))"
equation "d788 = abs(( 0 mm ) * ( cos(149.638806595178 deg) ) - ( 1 ) * spokeWidth / 2 * ( sin(149.638806595178 deg) ))"
equation "d789 = abs(( 0 mm ) * ( sin(149.638806595178 deg) ) + ( 1 ) * spokeWidth / 2 * ( cos(149.638806595178 deg) ))"
equation "d790 = -( spokeDepth )"
equation "d792 = abs(( 0 mm ) * ( cos(-149.638806595178 deg) ) - ( -1 ) * spokeWidth / 2 * ( sin(-149.638806595178 deg) ))"
equation "d793 = abs(( 0 mm ) * ( sin(-149.638806595178 deg) ) + ( -1 ) * spokeWidth / 2 * ( cos(-149.638806595178 deg) ))"
equation "d794 = abs(( bodyWidth ) * ( cos(-149.638806595178 deg) ) - ( -1 ) * spokeWidth / 2 * ( sin(-149.638806595178 deg) ))"
equation "d795 = abs(( bodyWidth ) * ( sin(-149.638806595178 deg) ) + ( -1 ) * spokeWidth / 2 * ( cos(-149.638806595178 deg) ))"
equation "d796 = abs(( bodyWidth ) * ( cos(-149.638806595178 deg) ) - ( 1 ) * spokeWidth / 2 * ( sin(-149.638806595178 deg) ))"
equation "d797 = abs(( bodyWidth ) * ( sin(-149.638806595178 deg) ) + ( 1 ) * spokeWidth / 2 * ( cos(-149.638806595178 deg) ))"
equation "d798 = abs(( 0 mm ) * ( cos(-149.638806595178 deg) ) - ( 1 ) * spokeWidth / 2 * ( sin(-149.638806595178 deg) ))"
equation "d799 = abs(( 0 mm ) * ( sin(-149.638806595178 deg) ) + ( 1 ) * spokeWidth / 2 * ( cos(-149.638806595178 deg) ))"
equation "d800 = -( spokeDepth )"
equation "d802 = abs(( 0 mm ) * ( cos(-106.324949936895 deg) ) - ( -1 ) * spokeWidth / 2 * ( sin(-106.324949936895 deg) ))"
equation "d803 = abs(( 0 mm ) * ( sin(-106.324949936895 deg) ) + ( -1 ) * spokeWidth / 2 * ( cos(-106.324949936895 deg) ))"
equation "d804 = abs(( bodyWidth ) * ( cos(-106.324949936895 deg) ) - ( -1 ) * spokeWidth / 2 * ( sin(-106.324949936895 deg) ))"
equation "d805 = abs(( bodyWidth ) * ( sin(-106.324949936895 deg) ) + ( -1 ) * spokeWidth / 2 * ( cos(-106.324949936895 deg) ))"
equation "d806 = abs(( bodyWidth ) * ( cos(-106.324949936895 deg) ) - ( 1 ) * spokeWidth / 2 * ( sin(-106.324949936895 deg) ))"
equation "d807 = abs(( bodyWidth ) * ( sin(-106.324949936895 deg) ) + ( 1 ) * spokeWidth / 2 * ( cos(-106.324949936895 deg) ))"
equation "d808 = abs(( 0 mm ) * ( cos(-106.324949936895 deg) ) - ( 1 ) * spokeWidth / 2 * ( sin(-106.324949936895 deg) ))"
equation "d809 = abs(( 0 mm ) * ( sin(-106.324949936895 deg) ) + ( 1 ) * spokeWidth / 2 * ( cos(-106.324949936895 deg) ))"
equation "d810 = -( spokeDepth )"
equation "d812 = bodyWidth"
equation "d813 = bodyLength"
equation "d816 = rootRadius"
equation "d817 = -qFront"
equation "d819 = mountOpening"
equation "d820 = -( -qFront - hubFace )"
equation "d822 = -qFront"
equation "d824 = abs(mountCircle / ( 2 * sqrt(2) ))"
equation "d825 = abs(mountCircle / ( 2 * sqrt(2) ))"
equation "d826 = m4Clearance"
equation "d827 = abs(-mountCircle / ( 2 * sqrt(2) ))"
equation "d828 = abs(mountCircle / ( 2 * sqrt(2) ))"
equation "d829 = m4Clearance"
equation "d830 = abs(-mountCircle / ( 2 * sqrt(2) ))"
equation "d831 = abs(-mountCircle / ( 2 * sqrt(2) ))"
equation "d832 = m4Clearance"
equation "d833 = abs(mountCircle / ( 2 * sqrt(2) ))"
equation "d834 = abs(-mountCircle / ( 2 * sqrt(2) ))"
equation "d835 = m4Clearance"
equation "d836 = -( -qFront - hubFace )"
equation "d838 = abs(mountCircle / ( 2 * sqrt(2) ))"
equation "d839 = abs(mountCircle / ( 2 * sqrt(2) ))"
equation "d840 = 2 * ( nutAF ) / sqrt(3)"
equation "d841 = -( nutDepth )"
equation "d843 = abs(-mountCircle / ( 2 * sqrt(2) ))"
equation "d844 = abs(mountCircle / ( 2 * sqrt(2) ))"
equation "d845 = 2 * ( nutAF ) / sqrt(3)"
equation "d846 = -( nutDepth )"
equation "d848 = abs(-mountCircle / ( 2 * sqrt(2) ))"
equation "d849 = abs(-mountCircle / ( 2 * sqrt(2) ))"
equation "d850 = 2 * ( nutAF ) / sqrt(3)"
equation "d851 = -( nutDepth )"
equation "d853 = abs(mountCircle / ( 2 * sqrt(2) ))"
equation "d854 = abs(-mountCircle / ( 2 * sqrt(2) ))"
equation "d855 = 2 * ( nutAF ) / sqrt(3)"
equation "d856 = -( nutDepth )"
equation "d858 = abs(( -8 mm - 13 mm ) / sqrt(2))"
equation "d859 = abs(( -8 mm + 13 mm ) / sqrt(2))"
equation "d860 = abs(( -30 mm - 13 mm ) / sqrt(2))"
equation "d861 = abs(( -30 mm + 13 mm ) / sqrt(2))"
equation "d862 = abs(( -30 mm + 13 mm ) / sqrt(2))"
equation "d863 = abs(( -30 mm - 13 mm ) / sqrt(2))"
equation "d864 = abs(( -8 mm + 13 mm ) / sqrt(2))"
equation "d865 = abs(( -8 mm - 13 mm ) / sqrt(2))"
equation "d866 = mountOD"
equation "d868 = bedRelief"
equation "d869 = tubeCornerChamfer"
equation "d870 = tubeRimChamfer"
equation "d873 = bodyWidth / 2"
equation "d875 = abs(( 1 ) * ( ( 1 ) * cordStation ) + ( 0 ) * ( 0 mm ))"
equation "d877 = -( wall )"
equation "d879 = bedRelief"
equation "d882 = bodyWidth / 2"
equation "d884 = abs(( -1 ) * ( ( 1 ) * cordStation ) + ( 0 ) * ( 0 mm ))"
equation "d886 = -( wall )"
equation "d888 = bedRelief"
equation "d889 = bedRelief"
equation "d890 = tubeCornerChamfer"
equation "d891 = tubeRimChamfer"
equation "d894 = bodyWidth / 2"
equation "d896 = abs(( 1 ) * ( ( -1 ) * cordStation ) + ( 0 ) * ( 0 mm ))"
equation "d898 = -( wall )"
equation "d900 = bedRelief"
equation "d903 = bodyWidth / 2"
equation "d905 = abs(( -1 ) * ( ( -1 ) * cordStation ) + ( 0 ) * ( 0 mm ))"
equation "d907 = -( wall )"
equation "d909 = bedRelief"
equation "d910 = qRearBase"
equation "d912 = coreOD"
equation "d913 = shoulder + rearSeatDepth"
equation "d915 = qRearBase"
equation "d917 = raceRelief"
equation "d918 = shoulder + rearSeatDepth"
equation "d920 = qRearBearing"
equation "d922 = seatDiameter"
equation "d923 = rearSeatDepth"
equation "d925 = qRearBase"
equation "d927 = supportCircle / 2"
equation "d928 = m3Clearance"
equation "d929 = shoulder + rearSeatDepth"
equation "d933 = entryChamfer"
equation "d934 = bedRelief"
equation "d935 = qFront - capThickness"
equation "d937 = coreOD"
equation "d938 = raceRelief"
equation "d939 = capThickness"
equation "d941 = qFront - capThickness"
equation "d943 = supportCircle / 2"
equation "d944 = m3Clearance"
equation "d945 = capThickness"
equation "d949 = bedRelief"
equation "d950 = qRearEnd"
equation "d952 = coreOD"
equation "d953 = raceRelief"
equation "d954 = capThickness"
equation "d956 = qRearEnd"
equation "d958 = supportCircle / 2"
equation "d959 = m3Clearance"
equation "d960 = capThickness"
equation "d964 = bedRelief"
equation "d965 = hubFace - adapterThickness"
equation "d967 = mountOD"
equation "d968 = adapterThickness"
equation "d970 = hubFace"
equation "d972 = pilotDiameter"
equation "d973 = pilotInside"
equation "d974 = pilotHeight"
equation "d976 = hubFace - adapterThickness"
equation "d978 = shaftClearance"
equation "d979 = adapterThickness"
equation "d981 = hubFace - adapterThickness"
equation "d983 = abs(mountCircle / ( 2 * sqrt(2) ))"
equation "d984 = abs(mountCircle / ( 2 * sqrt(2) ))"
equation "d985 = m4Clearance"
equation "d986 = abs(-mountCircle / ( 2 * sqrt(2) ))"
equation "d987 = abs(mountCircle / ( 2 * sqrt(2) ))"
equation "d988 = m4Clearance"
equation "d989 = abs(-mountCircle / ( 2 * sqrt(2) ))"
equation "d990 = abs(-mountCircle / ( 2 * sqrt(2) ))"
equation "d991 = m4Clearance"
equation "d992 = abs(mountCircle / ( 2 * sqrt(2) ))"
equation "d993 = abs(-mountCircle / ( 2 * sqrt(2) ))"
equation "d994 = m4Clearance"
equation "d995 = adapterThickness"
equation "d997 = abs(hubHoleSpacing / sqrt(2))"
equation "d998 = sleeveOD + sleeveAllowance"
equation "d999 = abs(hubHoleSpacing / sqrt(2))"
equation "d1000 = sleeveOD + sleeveAllowance"
equation "d1001 = abs(-hubHoleSpacing / sqrt(2))"
equation "d1002 = sleeveOD + sleeveAllowance"
equation "d1003 = abs(-hubHoleSpacing / sqrt(2))"
equation "d1004 = sleeveOD + sleeveAllowance"
equation "d1005 = adapterThickness"
equation "d1007 = entryChamfer"
equation "d1008 = bedRelief"
equation "d1009 = qFront"
equation "d1011 = bearingOD"
equation "d1012 = bearingID"
equation "d1013 = bearingWidth"
equation "d1015 = qRearBearing"
equation "d1017 = bearingOD"
equation "d1018 = bearingID"
equation "d1019 = bearingWidth"
equation "d1026 = qFront - 4 mm"
equation "d1032 = qFront + bearingWidth"
equation "d1038 = qFront - 13 mm"
equation "d1044 = qFront + bearingWidth + 4 mm"
equation "d1053 = qFrontBack"
equation "d1055 = supportCircle / 2"
equation "d1056 = supportSpacerOD"
equation "d1058 = supportSpacer"
equation "d1062 = hubFace - adapterThickness"
equation "d1064 = abs(hubHoleSpacing / sqrt(2))"
equation "d1065 = sleeveOD"
equation "d1067 = adapterThickness"
equation "d1069 = hubFace - adapterThickness"
equation "d1071 = abs(hubHoleSpacing / sqrt(2))"
equation "d1072 = sleeveOD"
equation "d1074 = adapterThickness"
equation "d1076 = hubFace - adapterThickness"
equation "d1078 = abs(-hubHoleSpacing / sqrt(2))"
equation "d1079 = sleeveOD"
equation "d1081 = adapterThickness"
equation "d1083 = hubFace - adapterThickness"
equation "d1085 = abs(-hubHoleSpacing / sqrt(2))"
equation "d1086 = sleeveOD"
equation "d1088 = adapterThickness"
equation "d1090 = hubFace"
equation "d1096 = hubFace + 8 mm"
equation "d1102 = hubFace"
equation "d1104 = abs(hubHoleSpacing / sqrt(2))"
equation "d1106 = abs(hubHoleSpacing / sqrt(2))"
equation "d1108 = abs(-hubHoleSpacing / sqrt(2))"
equation "d1110 = abs(-hubHoleSpacing / sqrt(2))"
equation "d1114 = hubFace - adapterThickness - 1 mm"
equation "d1116 = abs(hubHoleSpacing / sqrt(2))"
equation "d1120 = hubFace - adapterThickness - 5 mm"